Autodesk Inventor part; units mm, degrees
(part 2 of 2)
sketch "Skizze21" plane through (14.5, 0, 0) normal (1, 0, 0) x (0, 0, -1)
  arc A0 (-19.975, -0.9997) -> (-19.8855, -2.1374) centre (0, 0) ccw projected
  arc A1 (-19.5727, -4.1122) -> (-19.8855, -2.1374) centre (-19.7538, -3.1287) ccw projected
  arc A2 (-19.5727, -4.1122) -> (-19.3063, -5.2219) centre (0, 0) ccw projected
  arc A3 (-18.6884, -7.1234) -> (-19.3063, -5.2219) centre (-19.0211, -6.1803) ccw projected
  arc A4 (-18.6884, -7.1234) -> (-18.2517, -8.1777) centre (0, 0) ccw projected
  arc A5 (-17.344, -9.9592) -> (-18.2517, -8.1777) centre (-17.8201, -9.0798) ccw projected
  arc A6 (-17.344, -9.9592) -> (-16.7477, -10.9322) centre (0, 0) ccw projected
  arc A7 (-15.5725, -12.5498) -> (-16.7477, -10.9322) centre (-16.1803, -11.7557) ccw projected
  arc A8 (-15.5725, -12.5498) -> (-14.8313, -13.4176) centre (0, 0) ccw projected
  arc A9 (-13.4176, -14.8313) -> (-14.8313, -13.4176) centre (-14.1421, -14.1421) ccw projected
  arc A10 (-13.4176, -14.8313) -> (-12.5498, -15.5725) centre (0, 0) ccw projected
  arc A11 (-10.9322, -16.7477) -> (-12.5498, -15.5725) centre (-11.7557, -16.1803) ccw projected
  arc A12 (-10.9322, -16.7477) -> (-9.9592, -17.344) centre (0, 0) ccw projected
  arc A13 (-8.1777, -18.2517) -> (-9.9592, -17.344) centre (-9.0798, -17.8201) ccw projected
  arc A14 (-8.1777, -18.2517) -> (-7.1234, -18.6884) centre (0, 0) ccw projected
  arc A15 (-5.2219, -19.3063) -> (-7.1234, -18.6884) centre (-6.1803, -19.0211) ccw projected
  arc A16 (-5.2219, -19.3063) -> (-4.1122, -19.5727) centre (0, 0) ccw projected
  arc A17 (-2.1374, -19.8855) -> (-4.1122, -19.5727) centre (-3.1287, -19.7538) ccw projected
  arc A18 (-2.1374, -19.8855) -> (-0.9997, -19.975) centre (0, 0) ccw projected
  arc A19 (0.9997, -19.975) -> (-0.9997, -19.975) centre (0, -20) ccw projected
  arc A20 (0.9997, -19.975) -> (2.1374, -19.8855) centre (0, 0) ccw projected
  arc A21 (4.1122, -19.5727) -> (2.1374, -19.8855) centre (3.1287, -19.7538) ccw projected
  arc A22 (4.1122, -19.5727) -> (5.2219, -19.3063) centre (0, 0) ccw projected
  arc A23 (7.1234, -18.6884) -> (5.2219, -19.3063) centre (6.1803, -19.0211) ccw projected
  arc A24 (7.1234, -18.6884) -> (8.1777, -18.2517) centre (0, 0) ccw projected
  arc A25 (9.9592, -17.344) -> (8.1777, -18.2517) centre (9.0798, -17.8201) ccw projected
  arc A26 (9.9592, -17.344) -> (10.9322, -16.7477) centre (0, 0) ccw projected
  arc A27 (12.5498, -15.5725) -> (10.9322, -16.7477) centre (11.7557, -16.1803) ccw projected
  arc A28 (12.5498, -15.5725) -> (13.4176, -14.8313) centre (0, 0) ccw projected
  arc A29 (14.8313, -13.4176) -> (13.4176, -14.8313) centre (14.1421, -14.1421) ccw projected
  arc A30 (14.8313, -13.4176) -> (15.5725, -12.5498) centre (0, 0) ccw projected
  arc A31 (16.7477, -10.9322) -> (15.5725, -12.5498) centre (16.1803, -11.7557) ccw projected
  arc A32 (16.7477, -10.9322) -> (17.344, -9.9592) centre (0, 0) ccw projected
  arc A33 (18.2517, -8.1777) -> (17.344, -9.9592) centre (17.8201, -9.0798) ccw projected
  arc A34 (18.2517, -8.1777) -> (18.6884, -7.1234) centre (0, 0) ccw projected
  arc A35 (19.3063, -5.2219) -> (18.6884, -7.1234) centre (19.0211, -6.1803) ccw projected
  arc A36 (19.3063, -5.2219) -> (19.5727, -4.1122) centre (0, 0) ccw projected
  arc A37 (19.8855, -2.1374) -> (19.5727, -4.1122) centre (19.7538, -3.1287) ccw projected
  arc A38 (19.8855, -2.1374) -> (19.975, -0.9997) centre (0, 0) ccw projected
  arc A39 (19.975, 0.9997) -> (19.975, -0.9997) centre (20, 0) ccw projected
  arc A40 (19.975, 0.9997) -> (19.8855, 2.1374) centre (0, 0) ccw projected
  arc A41 (19.5727, 4.1122) -> (19.8855, 2.1374) centre (19.7538, 3.1287) ccw projected
  arc A42 (19.5727, 4.1122) -> (19.3063, 5.2219) centre (0, 0) ccw projected
  arc A43 (18.6884, 7.1234) -> (19.3063, 5.2219) centre (19.0211, 6.1803) ccw projected
  arc A44 (18.6884, 7.1234) -> (18.2517, 8.1777) centre (0, 0) ccw projected
  arc A45 (17.344, 9.9592) -> (18.2517, 8.1777) centre (17.8201, 9.0798) ccw projected
  arc A46 (17.344, 9.9592) -> (16.7477, 10.9322) centre (0, 0) ccw projected
  arc A47 (15.5725, 12.5498) -> (16.7477, 10.9322) centre (16.1803, 11.7557) ccw projected
  arc A48 (15.5725, 12.5498) -> (14.8313, 13.4176) centre (0, 0) ccw projected
  arc A49 (13.4176, 14.8313) -> (14.8313, 13.4176) centre (14.1421, 14.1421) ccw projected
  arc A50 (13.4176, 14.8313) -> (12.5498, 15.5725) centre (0, 0) ccw projected
  arc A51 (10.9322, 16.7477) -> (12.5498, 15.5725) centre (11.7557, 16.1803) ccw projected
  arc A52 (10.9322, 16.7477) -> (9.9592, 17.344) centre (0, 0) ccw projected
  arc A53 (8.1777, 18.2517) -> (9.9592, 17.344) centre (9.0798, 17.8201) ccw projected
  arc A54 (8.1777, 18.2517) -> (7.1234, 18.6884) centre (0, 0) ccw projected
  arc A55 (5.2219, 19.3063) -> (7.1234, 18.6884) centre (6.1803, 19.0211) ccw projected
  arc A56 (5.2219, 19.3063) -> (4.1122, 19.5727) centre (0, 0) ccw projected
  arc A57 (2.1374, 19.8855) -> (4.1122, 19.5727) centre (3.1287, 19.7538) ccw projected
  arc A58 (2.1374, 19.8855) -> (0.9997, 19.975) centre (0, 0) ccw projected
  arc A59 (-0.9997, 19.975) -> (0.9997, 19.975) centre (0, 20) ccw projected
  arc A60 (-0.9997, 19.975) -> (-2.1374, 19.8855) centre (0, 0) ccw projected
  arc A61 (-4.1122, 19.5727) -> (-2.1374, 19.8855) centre (-3.1287, 19.7538) ccw projected
  arc A62 (-4.1122, 19.5727) -> (-5.2219, 19.3063) centre (0, 0) ccw projected
  arc A63 (-7.1234, 18.6884) -> (-5.2219, 19.3063) centre (-6.1803, 19.0211) ccw projected
  arc A64 (-7.1234, 18.6884) -> (-8.1777, 18.2517) centre (0, 0) ccw projected
  arc A65 (-9.9592, 17.344) -> (-8.1777, 18.2517) centre (-9.0798, 17.8201) ccw projected
  arc A66 (-9.9592, 17.344) -> (-10.9322, 16.7477) centre (0, 0) ccw projected
  arc A67 (-12.5498, 15.5725) -> (-10.9322, 16.7477) centre (-11.7557, 16.1803) ccw projected
  arc A68 (-12.5498, 15.5725) -> (-13.4176, 14.8313) centre (0, 0) ccw projected
  arc A69 (-14.8313, 13.4176) -> (-13.4176, 14.8313) centre (-14.1421, 14.1421) ccw projected
  arc A70 (-14.8313, 13.4176) -> (-15.5725, 12.5498) centre (0, 0) ccw projected
  arc A71 (-16.7477, 10.9322) -> (-15.5725, 12.5498) centre (-16.1803, 11.7557) ccw projected
  arc A72 (-16.7477, 10.9322) -> (-17.344, 9.9592) centre (0, 0) ccw projected
  arc A73 (-18.2517, 8.1777) -> (-17.344, 9.9592) centre (-17.8201, 9.0798) ccw projected
  arc A74 (-18.2517, 8.1777) -> (-18.6884, 7.1234) centre (0, 0) ccw projected
  arc A75 (-19.3063, 5.2219) -> (-18.6884, 7.1234) centre (-19.0211, 6.1803) ccw projected
  arc A76 (-19.3063, 5.2219) -> (-19.5727, 4.1122) centre (0, 0) ccw projected
  arc A77 (-19.8855, 2.1374) -> (-19.5727, 4.1122) centre (-19.7538, 3.1287) ccw projected
  arc A78 (-19.8855, 2.1374) -> (-19.975, 0.9997) centre (0, 0) ccw projected
  arc A79 (-19.975, -0.9997) -> (-19.975, 0.9997) centre (-20, 0) ccw projected
  line L0 (-5.5179, 13.5574) -> (-4.8492, 12.399) projected
  arc A80 (-4.8492, 12.399) -> (-3.6881, 11.9435) centre (-3.9831, 12.899) ccw projected
  arc A81 (3.6881, 11.9435) -> (-3.6881, 11.9435) centre (0, 0) ccw projected
  arc A82 (3.6881, 11.9435) -> (4.8492, 12.399) centre (3.9831, 12.899) ccw projected
  line L1 (4.8492, 12.399) -> (5.5179, 13.5574) projected
  arc A83 (5.5179, 13.5574) -> (5.1519, 14.9234) centre (4.6519, 14.0574) ccw projected
  line L2 (5.1519, 14.9234) -> (3.4199, 15.9234) projected
  arc A84 (3.0538, 17.2894) -> (3.4199, 15.9234) centre (3.9199, 16.7894) ccw projected
  line L3 (3.0538, 17.2894) -> (3.2538, 17.6358) projected
  arc A85 (4.6199, 18.0019) -> (3.2538, 17.6358) centre (4.1199, 17.1358) ccw projected
  line L4 (4.6199, 18.0019) -> (13.2801, 13.0019) projected
  arc A86 (13.6462, 11.6358) -> (13.2801, 13.0019) centre (12.7801, 12.1358) ccw projected
  line L5 (13.6462, 11.6358) -> (13.4462, 11.2894) projected
  arc A87 (12.0801, 10.9234) -> (13.4462, 11.2894) centre (12.5801, 11.7894) ccw projected
  line L6 (12.0801, 10.9234) -> (10.3481, 11.9234) projected
  arc A88 (10.3481, 11.9234) -> (8.9821, 11.5574) centre (9.8481, 11.0574) ccw projected
  line L7 (8.9821, 11.5574) -> (8.3133, 10.399) projected
  arc A89 (8.3133, 10.399) -> (8.4994, 9.1658) centre (9.1793, 9.899) ccw projected
  arc A90 (12.1875, 2.7778) -> (8.4994, 9.1658) centre (0, 0) ccw projected
  arc A91 (12.1875, 2.7778) -> (13.1624, 2) centre (13.1624, 3) ccw projected
  line L8 (13.1624, 2) -> (14.5, 2) projected
  arc A92 (14.5, 2) -> (15.5, 3) centre (14.5, 3) ccw projected
  line L9 (15.5, 3) -> (15.5, 5) projected
  arc A93 (16.5, 6) -> (15.5, 5) centre (16.5, 5) ccw projected
  line L10 (16.5, 6) -> (16.9, 6) projected
  arc A94 (17.9, 5) -> (16.9, 6) centre (16.9, 5) ccw projected
  line L11 (17.9, 5) -> (17.9, -5) projected
  arc A95 (16.9, -6) -> (17.9, -5) centre (16.9, -5) ccw projected
  line L12 (16.9, -6) -> (16.5, -6) projected
  arc A96 (15.5, -5) -> (16.5, -6) centre (16.5, -5) ccw projected
  line L13 (15.5, -5) -> (15.5, -3) projected
  arc A97 (15.5, -3) -> (14.5, -2) centre (14.5, -3) ccw projected
  line L14 (14.5, -2) -> (13.1624, -2) projected
  arc A98 (13.1624, -2) -> (12.1875, -2.7778) centre (13.1624, -3) ccw projected
  arc A99 (8.4994, -9.1658) -> (12.1875, -2.7778) centre (0, 0) ccw projected
  arc A100 (8.4994, -9.1658) -> (8.3133, -10.399) centre (9.1793, -9.899) ccw projected
  line L15 (8.3133, -10.399) -> (8.9821, -11.5574) projected
  arc A101 (8.9821, -11.5574) -> (10.3481, -11.9234) centre (9.8481, -11.0574) ccw projected
  line L16 (10.3481, -11.9234) -> (12.0801, -10.9234) projected
  arc A102 (13.4462, -11.2894) -> (12.0801, -10.9234) centre (12.5801, -11.7894) ccw projected
  line L17 (13.4462, -11.2894) -> (13.6462, -11.6358) projected
  arc A103 (13.2801, -13.0019) -> (13.6462, -11.6358) centre (12.7801, -12.1358) ccw projected
  line L18 (13.2801, -13.0019) -> (4.6199, -18.0019) projected
  arc A104 (3.2538, -17.6358) -> (4.6199, -18.0019) centre (4.1199, -17.1358) ccw projected
  line L19 (3.2538, -17.6358) -> (3.0538, -17.2894) projected
  arc A105 (3.4199, -15.9234) -> (3.0538, -17.2894) centre (3.9199, -16.7894) ccw projected
  line L20 (3.4199, -15.9234) -> (5.1519, -14.9234) projected
  arc A106 (5.1519, -14.9234) -> (5.5179, -13.5574) centre (4.6519, -14.0574) ccw projected
  line L21 (5.5179, -13.5574) -> (4.8492, -12.399) projected
  arc A107 (4.8492, -12.399) -> (3.6881, -11.9435) centre (3.9831, -12.899) ccw projected
  arc A108 (-3.6881, -11.9435) -> (3.6881, -11.9435) centre (0, 0) ccw projected
  arc A109 (-3.6881, -11.9435) -> (-4.8492, -12.399) centre (-3.9831, -12.899) ccw projected
  line L22 (-4.8492, -12.399) -> (-5.5179, -13.5574) projected
  arc A110 (-5.5179, -13.5574) -> (-5.1519, -14.9234) centre (-4.6519, -14.0574) ccw projected
  line L23 (-5.1519, -14.9234) -> (-3.4199, -15.9234) projected
  arc A111 (-3.0538, -17.2894) -> (-3.4199, -15.9234) centre (-3.9199, -16.7894) ccw projected
  line L24 (-3.0538, -17.2894) -> (-3.2538, -17.6358) projected
  arc A112 (-4.6199, -18.0019) -> (-3.2538, -17.6358) centre (-4.1199, -17.1358) ccw projected
  line L25 (-4.6199, -18.0019) -> (-13.2801, -13.0019) projected
  arc A113 (-13.6462, -11.6358) -> (-13.2801, -13.0019) centre (-12.7801, -12.1358) ccw projected
  line L26 (-13.6462, -11.6358) -> (-13.4462, -11.2894) projected
  arc A114 (-12.0801, -10.9234) -> (-13.4462, -11.2894) centre (-12.5801, -11.7894) ccw projected
  line L27 (-12.0801, -10.9234) -> (-10.3481, -11.9234) projected
  arc A115 (-10.3481, -11.9234) -> (-8.9821, -11.5574) centre (-9.8481, -11.0574) ccw projected
  line L28 (-8.9821, -11.5574) -> (-8.3133, -10.399) projected
  arc A116 (-8.3133, -10.399) -> (-8.4994, -9.1658) centre (-9.1793, -9.899) ccw projected
  arc A117 (-12.1875, -2.7778) -> (-8.4994, -9.1658) centre (0, 0) ccw projected
  arc A118 (-12.1875, -2.7778) -> (-13.1624, -2) centre (-13.1624, -3) ccw projected
  line L29 (-13.1624, -2) -> (-14.5, -2) projected
  arc A119 (-14.5, -2) -> (-15.5, -3) centre (-14.5, -3) ccw projected
  line L30 (-15.5, -3) -> (-15.5, -5) projected
  arc A120 (-16.5, -6) -> (-15.5, -5) centre (-16.5, -5) ccw projected
  line L31 (-16.5, -6) -> (-16.9, -6) projected
  arc A121 (-17.9, -5) -> (-16.9, -6) centre (-16.9, -5) ccw projected
  line L32 (-17.9, -5) -> (-17.9, 5) projected
  arc A122 (-16.9, 6) -> (-17.9, 5) centre (-16.9, 5) ccw projected
  line L33 (-16.9, 6) -> (-16.5, 6) projected
  arc A123 (-15.5, 5) -> (-16.5, 6) centre (-16.5, 5) ccw projected
  line L34 (-15.5, 5) -> (-15.5, 3) projected
  arc A124 (-15.5, 3) -> (-14.5, 2) centre (-14.5, 3) ccw projected
  line L35 (-14.5, 2) -> (-13.1624, 2) projected
  arc A125 (-13.1624, 2) -> (-12.1875, 2.7778) centre (-13.1624, 3) ccw projected
  arc A126 (-8.4994, 9.1658) -> (-12.1875, 2.7778) centre (0, 0) ccw projected
  arc A127 (-8.4994, 9.1658) -> (-8.3133, 10.399) centre (-9.1793, 9.899) ccw projected
  line L36 (-8.3133, 10.399) -> (-8.9821, 11.5574) projected
  arc A128 (-8.9821, 11.5574) -> (-10.3481, 11.9234) centre (-9.8481, 11.0574) ccw projected
  line L37 (-10.3481, 11.9234) -> (-12.0801, 10.9234) projected
  arc A129 (-13.4462, 11.2894) -> (-12.0801, 10.9234) centre (-12.5801, 11.7894) ccw projected
  line L38 (-13.4462, 11.2894) -> (-13.6462, 11.6358) projected
  arc A130 (-13.2801, 13.0019) -> (-13.6462, 11.6358) centre (-12.7801, 12.1358) ccw projected
  line L39 (-13.2801, 13.0019) -> (-4.6199, 18.0019) projected
  arc A131 (-3.2538, 17.6358) -> (-4.6199, 18.0019) centre (-4.1199, 17.1358) ccw projected
  line L40 (-3.2538, 17.6358) -> (-3.0538, 17.2894) projected
  arc A132 (-3.4199, 15.9234) -> (-3.0538, 17.2894) centre (-3.9199, 16.7894) ccw projected
  line L41 (-3.4199, 15.9234) -> (-5.1519, 14.9234) projected
  arc A133 (-5.1519, 14.9234) -> (-5.5179, 13.5574) centre (-4.6519, 14.0574) ccw projected
  circle A134 centre (0, 0) radius 21.5
  circle A135 centre (-21.5, 0) radius 1
  circle A136 centre (-21.2353, -3.3633) radius 1
  circle A137 centre (-20.4477, -6.6439) radius 1
  circle A138 centre (-19.1566, -9.7608) radius 1
  circle A139 centre (-17.3939, -12.6374) radius 1
  circle A140 centre (-15.2028, -15.2028) radius 1
  circle A141 centre (-12.6374, -17.3939) radius 1
  circle A142 centre (-9.7608, -19.1566) radius 1
  circle A143 centre (-6.6439, -20.4477) radius 1
  circle A144 centre (-3.3633, -21.2353) radius 1
  circle A145 centre (0, -21.5) radius 1
  circle A146 centre (3.3633, -21.2353) radius 1
  circle A147 centre (6.6439, -20.4477) radius 1
  circle A148 centre (9.7608, -19.1566) radius 1
  circle A149 centre (12.6374, -17.3939) radius 1
  circle A150 centre (15.2028, -15.2028) radius 1
  circle A151 centre (17.3939, -12.6374) radius 1
  circle A152 centre (19.1566, -9.7608) radius 1
  circle A153 centre (20.4477, -6.6439) radius 1
  circle A154 centre (21.2353, -3.3633) radius 1
  circle A155 centre (21.5, 0) radius 1
  circle A156 centre (21.2353, 3.3633) radius 1
  circle A157 centre (20.4477, 6.6439) radius 1
  circle A158 centre (19.1566, 9.7608) radius 1
  circle A159 centre (17.3939, 12.6374) radius 1
  circle A160 centre (15.2028, 15.2028) radius 1
  circle A161 centre (12.6374, 17.3939) radius 1
  circle A162 centre (9.7608, 19.1566) radius 1
  circle A163 centre (6.6439, 20.4477) radius 1
  circle A164 centre (3.3633, 21.2353) radius 1
  circle A165 centre (0, 21.5) radius 1
  circle A166 centre (-3.3633, 21.2353) radius 1
  circle A167 centre (-6.6439, 20.4477) radius 1
  circle A168 centre (-9.7608, 19.1566) radius 1
  circle A169 centre (-12.6374, 17.3939) radius 1
  circle A170 centre (-15.2028, 15.2028) radius 1
  circle A171 centre (-17.3939, 12.6374) radius 1
  circle A172 centre (-19.1566, 9.7608) radius 1
  circle A173 centre (-20.4477, 6.6439) radius 1
  circle A174 centre (-21.2353, 3.3633) radius 1
  point P0 (-14.4794, 15.8933)
  point P1 (-15.8933, 14.4794)
  point P2 (-21.4767, 0.9997)
  point P3 (-21.4767, -0.9997)
  point P4 (-21.3687, -2.3723)
  point P5 (-21.0559, -4.3471)
  point P6 (-20.7345, -5.6859)
  point P7 (-20.1167, -7.5875)
  point P8 (-19.5898, -8.8595)
  point P9 (-18.6821, -10.641)
  point P10 (-17.9627, -11.8149)
  point P11 (-16.7874, -13.4325)
  point P12 (-15.8933, -14.4794)
  point P13 (-14.4794, -15.8933)
  point P14 (-13.4325, -16.7874)
  point P15 (-11.8149, -17.9627)
  point P16 (-10.641, -18.6821)
  point P17 (-8.8595, -19.5898)
  point P18 (-7.5875, -20.1167)
  point P19 (-5.6859, -20.7345)
  point P20 (-4.3471, -21.0559)
  point P21 (-2.3723, -21.3687)
  point P22 (-0.9997, -21.4767)
  point P23 (0.9997, -21.4767)
  point P24 (2.3723, -21.3687)
  point P25 (4.3471, -21.0559)
  point P26 (5.6859, -20.7345)
  point P27 (7.5875, -20.1167)
  point P28 (8.8595, -19.5898)
  point P29 (10.641, -18.6821)
  point P30 (11.8149, -17.9627)
  point P31 (13.4325, -16.7874)
  point P32 (14.4794, -15.8933)
  point P33 (15.8933, -14.4794)
  point P34 (16.7874, -13.4325)
  point P35 (17.9627, -11.8149)
  point P36 (18.6821, -10.641)
  point P37 (19.5898, -8.8595)
  point P38 (20.7345, -5.6859)
  point P39 (20.1167, -7.5875)
  point P40 (21.0559, -4.3471)
  point P41 (21.3687, -2.3723)
  point P42 (21.4767, 0.9997)
  point P43 (21.4767, -0.9997)
  point P44 (21.3687, 2.3723)
  point P45 (21.0559, 4.3471)
  point P46 (20.7345, 5.6859)
  point P47 (20.1167, 7.5875)
  point P48 (19.5898, 8.8595)
  point P49 (18.6821, 10.641)
  point P50 (17.9627, 11.8149)
  point P51 (16.7874, 13.4325)
  point P52 (15.8933, 14.4794)
  point P53 (14.4794, 15.8933)
  point P54 (13.4325, 16.7874)
  point P55 (11.8149, 17.9627)
  point P56 (10.641, 18.6821)
  point P57 (8.8595, 19.5898)
  point P58 (7.5875, 20.1167)
  point P59 (5.6859, 20.7345)
  point P60 (4.3471, 21.0559)
  point P61 (2.3723, 21.3687)
  point P62 (0.9997, 21.4767)
  point P63 (-0.9997, 21.4767)
  point P64 (-2.3723, 21.3687)
  point P65 (-4.3471, 21.0559)
  point P66 (-5.6859, 20.7345)
  point P67 (-7.5875, 20.1167)
  point P68 (-8.8595, 19.5898)
  point P69 (-10.641, 18.6821)
  point P70 (-11.8149, 17.9627)
  point P71 (-13.4325, 16.7874)
  point P72 (-16.7874, 13.4325)
  point P73 (-17.9627, 11.8149)
  point P74 (-18.6821, 10.641)
  point P75 (-19.5898, 8.8595)
  point P76 (-20.1167, 7.5875)
  point P77 (-20.7345, 5.6859)
  point P78 (-21.0559, 4.3471)
  point P79 (-21.3687, 2.3723)
  dimension "d100" = 43
  dimension "d101" = 2
  dimension "d104" = 360
  constraints: 40 centre point, 1 coincident, 83 other
  measures "d101" diameter of A135
extrude "Extrusion22" add sketch "Skizze21" against normal up to surface (10 mm away) contours A155 A134 A154 A153 A152 A151 A150 A149 A148 A147 A146 A145 A144 A143 A142 A141 A140 A139 A138 A137 A136 A135 A174 A173 A172 A171 A170 A169 A168 A167 A166 A165 A164 A163 A162 A161 A160 A159 A158 A157 A156 bodies 3
equation "\"d55\" = 0.5 * d53"
equation "\"d61\" = 0.5 * d60"
